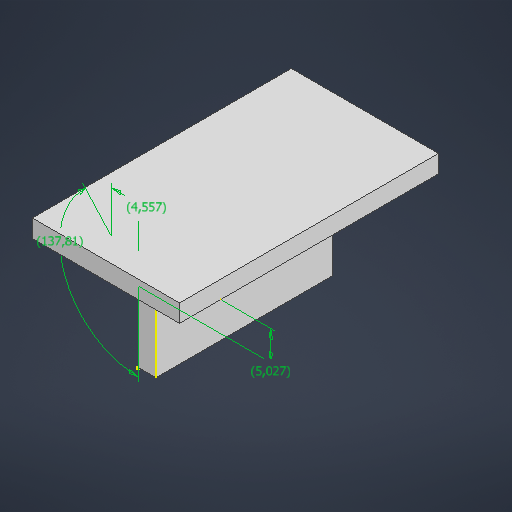
# Autodesk Inventor part: lampe2
Saved by Autodesk Inventor 2026 (Build 300175000, 175)
## iProperties
Created: 2026-10-28
Part Number: lampe2
Material: Generic
Document SubType Name: Modeling
Designer: alexp
Density: 1 g/cm^3
Appearance: Default
Author: alexp
Autodesk Inventor part; units mm, degrees
ref_plane "YZ Plane" through (0, 0, 0) normal (1, 0, 0) x (0, 1, 0)
ref_plane "XZ Plane" through (0, 0, 0) normal (0, 1, 0) x (-1, 0, 0)
ref_plane "XY Plane" through (0, 0, 0) normal (0, 0, 1) x (1, 0, 0)
sketch "Sketch1" plane through (0, 0, 0) normal (1, 0, 0) x (0, 1, 0)
  line L0 (20, 14.09) -> (0, 14.09)
  line L1 (0, 14.09) -> (0, -15.91)
  line L2 (0, -15.91) -> (20, -15.91)
  line L3 (20, -15.91) -> (20, 14.09)
  point P0 (0, 0)
  dimension "d0" = 20
  dimension "d1" = 30
  constraints: 8 end point, 2 parallel, 1 horizontal, 1 perpendicular
  measures "d0" distance between parallel lines of L1 L3
  measures "d1" distance between parallel lines of L2 L0
extrude "Extrusion1" add sketch "Sketch1" along normal blind 3
sketch "Sketch2" plane through (0, 0, -15.91) normal (0, 0, -1) x (-1, 0, 0)
  point P0 (0, 0)
sketch "Sketch3" plane through (0, 20, 14.09) normal (0, 1, 0) x (1, 0, 0)
  line L0 (14, -7) -> (-11, -7)
  line L1 (-11, -7) -> (-11, 37)
  line L2 (-11, 37) -> (14, 37)
  line L3 (14, 37) -> (14, -7)
  line L4 (0, 0) -> (3, 0) projected
  line L5 (0, 30) -> (0, 0) projected
  line L6 (3, 30) -> (3, 0) projected
  line L7 (0, 30) -> (3, 30) projected
  point P0 (0, 14.09)
  point P1 (1.5, 0)
  point P2 (1.5, 37)
  point P3 (1.5, 30)
  dimension "d4" = 44
  dimension "d5" = 25
  dimension "d6" = 7
  dimension "d7" = 11
  dimension "d8" = 11
  dimension "d9" = 7
  constraints: 8 end point, 3 midpoint, 2 parallel, 1 horizontal, 1 perpendicular
  measures "d4" distance between parallel lines of L2 L0
  measures "d5" distance between parallel lines of L1 L3
  measures "d6" distance from line of point (1.5, 0) L0
  measures "d7" distance between parallel lines of L1 L5
  measures "d8" distance between parallel lines of L3 L6
  measures "d9" distance of point (1.5, 37) point (1.5, 30)
extrude "Extrusion2" add sketch "Sketch3" against normal blind 3
sketch "Sketch14" plane through (3, 0, -15.91) normal (0, 0, -1) x (-1, 0, 0)
  point P0 (3, 0)
sketch "Sketch15" plane through (3, 0, -15.91) normal (0, 0, -1) x (-1, 0, 0)
  line L0 (3, 17) -> (3, 0) projected
  line L1 (3, 17) -> (3, 11.9727)
  line L2 (3, 11.9727) -> (7.5566, 17)
  line L3 (14, 17) -> (-11, 17) projected
  line L4 (7.5566, 17) -> (3, 17)
  constraints: 6 end point, 2 point on line, 1 collinear
extrude "Extrusion6" add sketch "Sketch15" against normal blind 5
sketch "Sketch16" plane through (3, 0, -15.91) normal (0, 0, -1) x (-1, 0, 0)
  line L0 (3, 0) -> (3, 11.9727) projected
  line L1 (0, 0) -> (0, 17) projected
  line L2 (0, 17) -> (-4.557, 17)
  line L3 (-4.557, 17) -> (-4.557, 11.973)
  line L4 (-4.557, 11.973) -> (0, 11.973)
  line L5 (0, 11.973) -> (0, 17)
  line L6 (-4.557, 17) -> (0, 11.973)
  line L7 (0, 11.973) -> (0, 17)
  line L8 (0, 17) -> (-4.557, 17)
  point P0 (-2.2785, 17)
  point P1 (-2.2785, 11.973)
  point P2 (-4.557, 14.4865)
  dimension "d25" = 3
  dimension "d40" = 5.027
  dimension "d41" = 4.557
  constraints: 14 end point, 3 equal length, 3 midpoint, 2 perpendicular, 1 horizontal
  measures "d25" distance between parallel lines of L0 L1
  measures "d40" distance of point (-2.279, 17) point (-2.278, 11.973)
  measures "d41" distance from line of L1 point (-4.557, 14.486)
sketch "Sketch17" plane through (0, 0, 14.09) normal (0, 0, 1) x (1, 0, 0)
  line L0 (0, 17) -> (0, 0) projected
  line L1 (0, 17) -> (0, 12.2206)
  line L2 (-4.5566, 17) -> (0, 11.9727) projected
  line L3 (-4.5566, 17) -> (0, 17)
  line L4 (0, 11.9727) -> (0, 17)
  line L5 (-4.5566, 17) -> (0, 11.9727)
  constraints: 8 end point, 2 collinear, 1 perpendicular, 1 point on line
extrude "Extrusion7" add sketch "Sketch17" against normal blind 5
sketch "Sketch18" plane through (0, 0, 14.09) normal (0, 0, 1) x (1, 0, 0)
  line L0 (14, 17) -> (-11, 17) projected
  line L1 (2.8055, 17) -> (7.3704, 17)
  line L2 (3, 17) -> (3, 0) projected
  line L3 (3, 12.2206) -> (3, 17)
  line L4 (3, 17) -> (7.3704, 17)
  line L5 (0, 11.9727) -> (0, 17) projected
  line L6 (0, 11.9727) -> (-4.5566, 17) projected
  point P0 (0, 0)
  dimension "d28" = 137.812
  dimension "d29" = 5.0273
  dimension "d30" = 4.5566
  constraints: 6 end point, 3 point on line, 2 collinear
  measures "d28" angle of L5 L6
  measures "d29" distance from line of L5.start L0
  measures "d30" distance from line of L5 L6.end
sketch "Sketch19" plane through (0, 0, 14.09) normal (0, 0, 1) x (1, 0, 0)
  line L0 (3, 17) -> (3, 0) projected
  line L1 (3, 17) -> (7.557, 17)
  line L2 (14, 17) -> (-11, 17) projected
  line L3 (3, 11.973) -> (3, 17)
  line L4 (7.557, 17) -> (3, 11.973)
  point P0 (0, 0)
  point P1 (5.2785, 17)
  point P2 (3, 14.4865)
  point P3 (3, 11.973)
  dimension "d31" = 5.027
  dimension "d32" = 5.027
  dimension "d33" = 4.557
  constraints: 6 end point, 2 midpoint, 1 perpendicular, 1 point on line
  measures "d31" distance from line of L3.start L1
  measures "d32" vertical distance of L3.start point (5.279, 17)
  measures "d33" horizontal distance of L1.end point (3, 14.486)
extrude "Extrusion8" add sketch "Sketch19" against normal blind 5
extrude "Extrusion9" add sketch "Sketch16" against normal blind 5 fills toward (-2.2415, 14.5201) open curves L6
body "Solid1"
